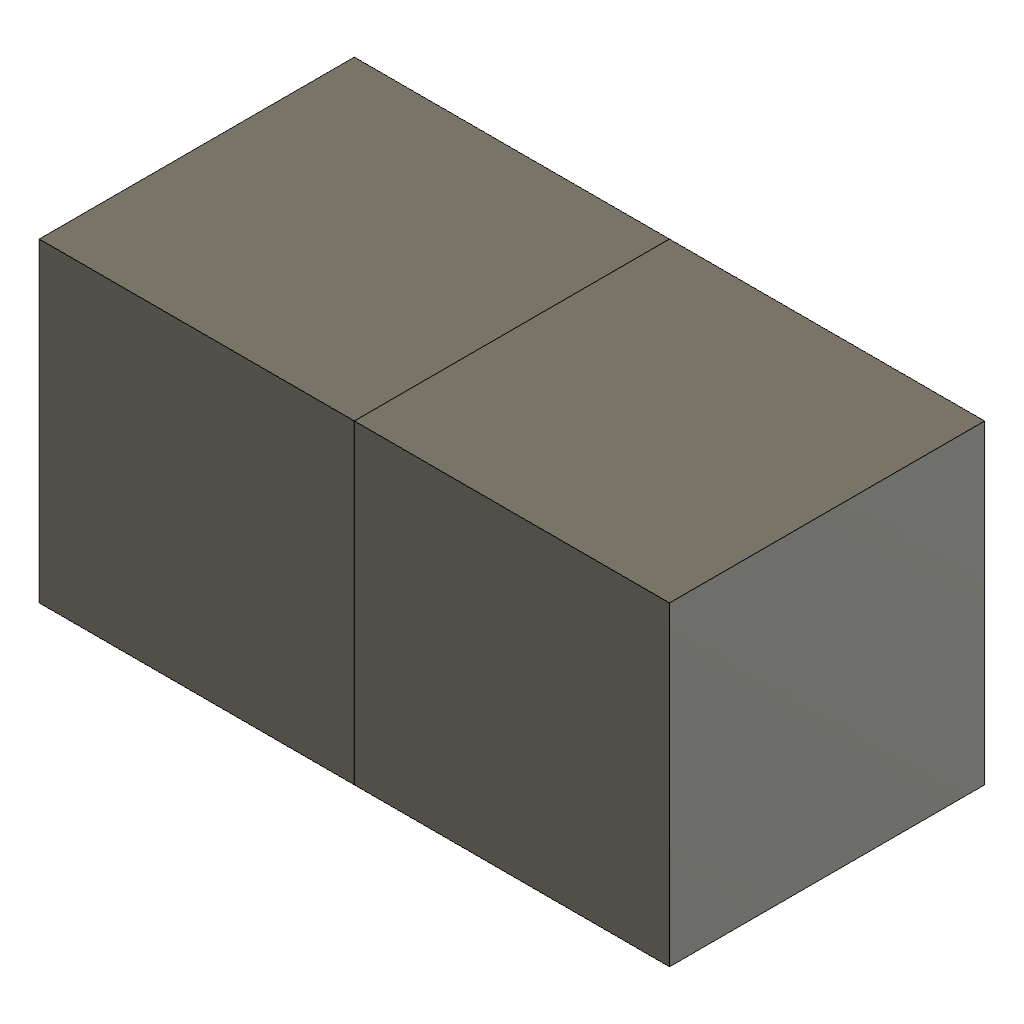
yz_no_extend (Autodesk Fusion 360 design; units mm, degrees)
part number: 2026-10-20-19-26-38-946
Autodesk Fusion 360 part; units mm, degrees
sketch "Sketch1" plane through (0, 0, 0) normal (0, 0, 1) x (1, 0, 0)
  line L0 (-20, -10) -> (20, -10)
  line L1 (20, -10) -> (20, 10)
  line L2 (20, 10) -> (-20, 10)
  line L3 (-20, 10) -> (-20, -10)
extrude "Extrude1" add sketch "Sketch1" along normal blind 20 makes body 1
split "ProbeSplit" by plane through (0, 0, 0) normal (1, 0, 0) bodies 1 makes body 2 at (13.3333, 10, 6.6667)
